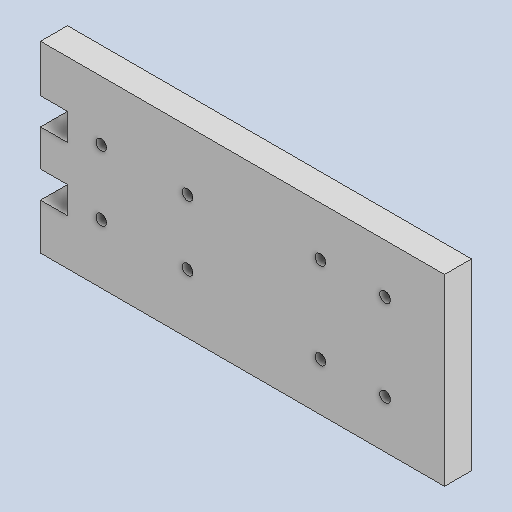
# Autodesk Inventor part: PelvBracketBottom
Saved by Autodesk Inventor 2025.2 (Build 292293000, 293)
## iProperties
Created: 2025-06-22
Part Number: PelvBracketBottom
Material: Generic
Document SubType Name: Modeling
Designer: ricoa
Density: 1 g/cm^3
Appearance: Default
Author: ricoa
Autodesk Inventor part; units mm, degrees
ref_plane "YZ Plane" through (0, 0, 0) normal (1, 0, 0) x (0, 1, 0)
ref_plane "XZ Plane" through (0, 0, 0) normal (0, 1, 0) x (-1, 0, 0)
ref_plane "XY Plane" through (0, 0, 0) normal (0, 0, 1) x (1, 0, 0)
sketch "Sketch1" plane through (0, 0, 0) normal (0, 0, 1) x (1, 0, 0)
  line L0 (2, 8.25) -> (2, 0.25) projected
  line L1 (2, -0.25) -> (2, -17) projected
  circle A0 centre (22.25, -14.5) radius 1 projected
  circle A1 centre (6.25, -14.5) radius 1 projected
  circle A2 centre (6.25, -2.5) radius 1 projected
  circle A3 centre (22.25, -2.5) radius 1 projected
  line L2 (2, -17) -> (2, -25.25) projected
  line L3 (2.1036, 8.5) -> (26.3964, 8.5) projected
  line L4 (26.3964, -25.5) -> (2.1036, -25.5) projected
  line L5 (2, 8.25) -> (2, 8.5)
  line L6 (2, 8.5) -> (2.1036, 8.5)
  line L7 (26.3964, 8.5) -> (26.5, 8.5)
  line L8 (2.1036, -25.5) -> (2, -25.5)
  line L9 (2, -25.5) -> (2, -25.25)
  line L10 (26.3964, -25.5) -> (26.5, -25.5)
  line L11 (28.5, -0.25) -> (28.5, -17) projected
  line L12 (0, -17) -> (0, -0.25) projected
  line L13 (24, 10.5) -> (4.5, 10.5) projected
  line L14 (26.5, 8.5) -> (68.5, 8.5)
  line L15 (68.5, -25.5) -> (26.5, -25.5)
  line L16 (69.866, 3.5214) -> (69.866, -20.7714) projected
  line L17 (-5, -25.5) -> (69.866, -25.5)
  line L18 (69.866, -25.5) -> (69.866, 8.5)
  line L19 (69.866, 8.5) -> (-5, 8.5)
  line L20 (-5, 8.5) -> (-5, -25.5)
  line L21 (68.5, 8.5) -> (68.5, -0.625)
  circle A4 centre (46.866, -0.625) radius 1 projected
  circle A5 centre (58.866, -0.625) radius 1 projected
  circle A6 centre (46.866, -16.625) radius 1 projected
  circle A7 centre (58.866, -16.625) radius 1 projected
  line L22 (-5, -8.9993) -> (-5, 29.0007) projected
  point P0 (0, 0)
  dimension "d5" = 42
  dimension "d12" = 0
  dimension "d13" = 0
  constraints: 26 end point, 3 perpendicular, 2 collinear, 2 horizontal, 2 parallel, 2 point on line, 1 vertical
  measures "d5" distance of L7.end L14.end
  measures "d12" distance between parallel lines of L18 L16
  measures "d13" distance between parallel lines of L20 L22
extrude "Extrusion1" add sketch "Sketch1" along normal blind 5
sketch "Sketch3" plane through (0, 0, 5) normal (0, 0, 1) x (1, 0, 0)
  line L0 (0, -17) -> (0, -12) projected
  line L1 (0, -12) -> (-5, -12) projected
  line L2 (-5, -17) -> (-5, -12) projected
  line L3 (0, -17) -> (-5, -17) projected
  line L4 (0, -5.25) -> (0, -0.25) projected
  line L5 (0, -0.25) -> (-5, -0.25) projected
  line L6 (-5, -5.25) -> (-5, -0.25) projected
  line L7 (0, -5.25) -> (-5, -5.25) projected
  point P0 (0, 0)
extrude "Extrusion3" cut sketch "Sketch3" against normal blind 5
body "Solid1"
